Autodesk Fusion 360 part; units mm, degrees
(part 5 of 9)
sketch "Adapter Washer 4 Outer" plane through (-21.2132, -21.2132, 0) normal (0.707107, 0.707107, 0) x (0, 0, 1) in component "REF M4 Adapter Fasteners"
  circle A0 centre (22.6274, -22.6274) radius 4.5
  circle A1 centre (22.6274, -22.6274) radius 2.15
  dimension "d1308" = 22.6274
  dimension "d1309" = 22.6274
  dimension "d1310" = 9
  dimension "d1311" = 4.3
  measures "d1308" horizontal distance of origin A0.centre
  measures "d1309" vertical distance of origin A0.centre
  measures "d1310" diameter of A0
  measures "d1311" diameter of A1
extrude "Adapter Washer 4" add sketch "Adapter Washer 4 Outer" along normal blind 1 separate body makes body 52 in component "REF M4 Adapter Fasteners"
ref_plane "WorkPlane16" through (-3.182, -3.182, 12.125) normal (0.707107, 0.707107, 0) x (0, 0, 1) in component "REF M4 Adapter Fasteners"
sketch "Adapter Nut Hex 4" plane through (-3.182, -3.182, 0) normal (0.707107, 0.707107, 0) x (0, 0, 1) in component "REF M4 Adapter Fasteners"
  circle A0 centre (22.6274, -22.6274) radius 4.0415 construction
  line L0 (26.6689, -22.6274) -> (24.6481, -19.1274)
  line L1 (24.6481, -19.1274) -> (20.6067, -19.1274)
  line L2 (20.6067, -19.1274) -> (18.586, -22.6274)
  line L3 (18.586, -22.6274) -> (20.6067, -26.1274)
  line L4 (20.6067, -26.1274) -> (24.6481, -26.1274)
  line L5 (24.6481, -26.1274) -> (26.6689, -22.6274)
  dimension "d1316" = 22.6274
  dimension "d1317" = 22.6274
  dimension "d1318" = 8.0829
  constraint coincident A0 L0.start
  constraint coincident A0 L0.end
  constraint coincident A0 L1.end
  constraint coincident A0 L2.end
  constraint coincident A0 L3.end
  constraint coincident A0 L4.end
  constraint equal L0 L1
  constraint equal L0 L2
  constraint equal L0 L3
  constraint equal L0 L4
  constraint equal L0 L5
  constraint horizontal L1
  measures "d1316" horizontal distance of origin A0.centre
  measures "d1317" vertical distance of origin A0.centre
  measures "d1318" diameter of A0
extrude "Adapter Nut 4" add sketch "Adapter Nut Hex 4" along normal blind 3.2 separate body makes body 53 in component "REF M4 Adapter Fasteners"
sketch "Nut Thread Clearance 4" plane through (-3.182, -3.182, 0) normal (0.707107, 0.707107, 0) x (0, 0, 1) in component "REF M4 Adapter Fasteners"
  circle A0 centre (22.6274, -22.6274) radius 2.15
  dimension "d1321" = 22.6274
  dimension "d1322" = 22.6274
  dimension "d1323" = 4.3
  measures "d1321" horizontal distance of origin A0.centre
  measures "d1322" vertical distance of origin A0.centre
  measures "d1323" diameter of A0
extrude "Nut Bore 4" cut sketch "Nut Thread Clearance 4" along normal blind 3.2 bodies 53 in component "REF M4 Adapter Fasteners"
ref_plane "WorkPlane1" through (0, 0, 12.125) normal (0.707107, 0.707107, 0) x (0, 0, 1) in component "REF M3 Support Fasteners"
sketch "M3 Pattern Axis" plane through (0, 0, 0) normal (0.707107, 0.707107, 0) x (0, 0, 1) in component "REF M3 Support Fasteners"
  circle A0 centre (0, 0) radius 0.5
  dimension "d1328" = 1
  measures "d1328" diameter of A0
ref_plane "WorkPlane2" through (-6.1518, -6.1518, 12.125) normal (0.707107, 0.707107, 0) x (0, 0, 1) in component "REF M3 Support Fasteners"
sketch "M3 Shank Profile" plane through (-6.1518, -6.1518, 0) normal (0.707107, 0.707107, 0) x (0, 0, 1) in component "REF M3 Support Fasteners"
  line L0 (0, 0) -> (17, 0) construction
  circle A0 centre (17, 0) radius 1.5
  dimension "d1331" = 17
  dimension "d1332" = 3
  constraint horizontal L0
  measures "d1331" distance of L0.start L0.end
  measures "d1332" diameter of A0
extrude "M3 Shank" add sketch "M3 Shank Profile" along normal blind 45 separate body makes body 54 in component "REF M3 Support Fasteners"
ref_plane "WorkPlane3" through (25.668, 25.668, 12.125) normal (0.707107, 0.707107, 0) x (0, 0, 1) in component "REF M3 Support Fasteners"
sketch "M3 Head Profile" plane through (25.668, 25.668, 0) normal (0.707107, 0.707107, 0) x (0, 0, 1) in component "REF M3 Support Fasteners"
  line L0 (0, 0) -> (17, 0) construction
  circle A0 centre (17, 0) radius 2.75
  dimension "d1337" = 17
  dimension "d1338" = 5.5
  constraint horizontal L0
  measures "d1337" distance of L0.start L0.end
  measures "d1338" diameter of A0
extrude "M3 Head" add sketch "M3 Head Profile" along normal blind 3 separate body makes body 55 in component "REF M3 Support Fasteners"
ref_plane "WorkPlane4" through (25.3144, 25.3144, 12.125) normal (0.707107, 0.707107, 0) x (0, 0, 1) in component "REF M3 Support Fasteners"
sketch "Rear M3 Washer Profile" plane through (25.3144, 25.3144, 0) normal (0.707107, 0.707107, 0) x (0, 0, 1) in component "REF M3 Support Fasteners"
  line L0 (0, 0) -> (17, 0) construction
  circle A0 centre (17, 0) radius 3.5
  circle A1 centre (17, 0) radius 1.65
  dimension "d1343" = 17
  dimension "d1344" = 7
  dimension "d1345" = 3.3
  constraint horizontal L0
  measures "d1343" distance of L0.start L0.end
  measures "d1344" diameter of A0
  measures "d1345" diameter of A1
extrude "Rear M3 Washer" add sketch "Rear M3 Washer Profile" along normal blind 0.5 separate body makes body 56 in component "REF M3 Support Fasteners"
ref_plane "WorkPlane5" through (-2.1213, -2.1213, 12.125) normal (0.707107, 0.707107, 0) x (0, 0, 1) in component "REF M3 Support Fasteners"
sketch "Front M3 Washer Profile" plane through (-2.1213, -2.1213, 0) normal (0.707107, 0.707107, 0) x (0, 0, 1) in component "REF M3 Support Fasteners"
  line L0 (0, 0) -> (17, 0) construction
  circle A0 centre (17, 0) radius 3.5
  circle A1 centre (17, 0) radius 1.65
  dimension "d1350" = 17
  dimension "d1351" = 7
  dimension "d1352" = 3.3
  constraint horizontal L0
  measures "d1350" distance of L0.start L0.end
  measures "d1351" diameter of A0
  measures "d1352" diameter of A1
extrude "Front M3 Washer" add sketch "Front M3 Washer Profile" along normal blind 0.5 separate body makes body 57 in component "REF M3 Support Fasteners"
ref_plane "WorkPlane6" through (-4.9497, -4.9497, 12.125) normal (0.707107, 0.707107, 0) x (0, 0, 1) in component "REF M3 Support Fasteners"
sketch "Front M3 Nyloc Envelope Profile" plane through (-4.9497, -4.9497, 0) normal (0.707107, 0.707107, 0) x (0, 0, 1) in component "REF M3 Support Fasteners"
  line L0 (0, 0) -> (17, 0) construction
  circle A0 centre (17, 0) radius 3.18
  circle A1 centre (17, 0) radius 1.65
  dimension "d1357" = 17
  dimension "d1358" = 6.36
  dimension "d1359" = 3.3
  constraint horizontal L0
  measures "d1357" distance of L0.start L0.end
  measures "d1358" diameter of A0
  measures "d1359" diameter of A1
extrude "Front M3 Nyloc Envelope" add sketch "Front M3 Nyloc Envelope Profile" along normal blind 4 separate body makes body 58 in component "REF M3 Support Fasteners"
pattern_circular "Three M3 Support Sets" count 3 over 360 about axis through (0, 0, 0) along (0.707107, 0.707107, 0) of "M3 Shank", "M3 Head", "Rear M3 Washer", "Front M3 Washer", "Front M3 Nyloc Envelope" makes body 59 at (26.4156, 3.7072, -9.1843) makes body 60 at (38.5579, 14.1923, -9.631) makes body 61 at (37.5691, 13.0597, -9.7105) makes body 62 at (10.487, -14.0225, -9.7105) makes body 63 at (8.453, -16.4669, -9.8079) makes body 64 at (5.063, 25.0597, -7.1178) makes body 65 at (15.0384, 39.126, -9.992) makes body 66 at (13.2406, 37.3882, -10.1537) makes body 67 at (-13.8416, 10.306, -10.1537) makes body 68 at (-16.243, 8.2291, -10.3563) in component "REF M3 Support Fasteners"
ref_plane "WorkPlane25" through (12.125, 0, 0) normal (0, -1, 0) x (1, 0, 0) in component "B Moving Body"
ref_plane "WorkPlane26" through (12.125, -75, 0) normal (0, -1, 0) x (1, 0, 0) in component "B Moving Body"
ref_plane "WorkPlane27" through (-24.7487, -24.7487, 12.125) normal (0.707107, 0.707107, 0) x (0, 0, 1) in component "B Moving Body"
ref_plane "WorkPlane33" through (0, 0, -35) normal (0, 0, 1) x (1, 0, 0) in component "A Housing"
sketch "PRINT-FIRST-A0-rim Crop Footprint" plane through (0, 0, -35) normal (0, 0, 1) x (1, 0, 0) in component "A Housing"
  line L0 (55, 66.5) -> (130, 66.5)
  line L1 (130, 66.5) -> (130, 75)
  line L2 (130, 75) -> (55, 75)
  line L3 (55, 75) -> (55, 66.5)
  dimension "d1451" = 55
  dimension "d1452" = 66.5
  dimension "d1453" = 130
  dimension "d1454" = 66.5
  dimension "d1455" = 130
  dimension "d1456" = 75
  dimension "d1457" = 55
  dimension "d1458" = 75
  measures "d1451" horizontal distance of origin L0.start
  measures "d1452" vertical distance of origin L0.start
  measures "d1453" horizontal distance of origin L0.end
  measures "d1454" vertical distance of origin L0.end
  measures "d1455" horizontal distance of origin L1.end
  measures "d1456" vertical distance of origin L1.end
  measures "d1457" horizontal distance of origin L2.end
  measures "d1458" vertical distance of origin L2.end
extrude "PRINT-FIRST-A0-rim Retain Full Bay" [suppressed] in component "A Housing"
ref_plane "WorkPlane34" through (63.7103, 63.7103, 12.125) normal (0.707107, 0.707107, 0) x (0, 0, 1) in component "A Housing"
sketch "PRINT-FIRST-A0-rim Level Bed Boundary" plane through (63.7103, 63.7103, 0) normal (0.707107, 0.707107, 0) x (0, 0, 1) in component "A Housing"
  line L0 (-200, -200) -> (200, -200)
  line L1 (200, -200) -> (200, 200)
  line L2 (200, 200) -> (-200, 200)
  line L3 (-200, 200) -> (-200, -200)
  line L4 (-200, -200) -> (200, 200) construction
  dimension "d1463" = 400
  dimension "d1464" = 400
  constraint horizontal L0
  constraint vertical L1
  constraint horizontal L2
  constraint vertical L3
  constraint midpoint origin L4
  measures "d1463" distance of L0.start L0.end
  measures "d1464" distance of L0.end L1.end
extrude "PRINT-FIRST-A0-rim Level Bed Intersect" [suppressed] in component "A Housing"
ref_plane "WorkPlane35" through (0, 0, 66.5) normal (0, 0, 1) x (1, 0, 0) in component "A Housing"
sketch "PRINT-FIRST-A90-brace Crop Footprint" plane through (0, 0, 66.5) normal (0, 0, 1) x (1, 0, 0) in component "A Housing"
  line L0 (48, -35) -> (130, -35)
  line L1 (130, -35) -> (130, 35)
  line L2 (130, 35) -> (48, 35)
  line L3 (48, 35) -> (48, -35)
  dimension "d1469" = 48
  dimension "d1470" = 35
  dimension "d1471" = 130
  dimension "d1472" = 35
  dimension "d1473" = 130
  dimension "d1474" = 35
  dimension "d1475" = 48
  dimension "d1476" = 35
  measures "d1469" horizontal distance of origin L0.start
  measures "d1470" vertical distance of origin L0.start
  measures "d1471" horizontal distance of origin L0.end
  measures "d1472" vertical distance of origin L0.end
  measures "d1473" horizontal distance of origin L1.end
  measures "d1474" vertical distance of origin L1.end
  measures "d1475" horizontal distance of origin L2.end
  measures "d1476" vertical distance of origin L2.end
extrude "PRINT-FIRST-A90-brace Retain Full Bay" [suppressed] in component "A Housing"
ref_plane "WorkPlane36" through (35.426, 35.426, 12.125) normal (0.707107, 0.707107, 0) x (0, 0, 1) in component "A Housing"
sketch "PRINT-FIRST-A90-brace Level Bed Boundary" plane through (35.426, 35.426, 0) normal (0.707107, 0.707107, 0) x (0, 0, 1) in component "A Housing"
  line L0 (-200, -200) -> (200, -200)
  line L1 (200, -200) -> (200, 200)
  line L2 (200, 200) -> (-200, 200)
  line L3 (-200, 200) -> (-200, -200)
  line L4 (-200, -200) -> (200, 200) construction
  dimension "d1481" = 400
  dimension "d1482" = 400
  constraint horizontal L0
  constraint vertical L1
  constraint horizontal L2
  constraint vertical L3
  constraint midpoint origin L4
  measures "d1481" distance of L0.start L0.end
  measures "d1482" distance of L0.end L1.end
extrude "PRINT-FIRST-A90-brace Level Bed Intersect" [suppressed] in component "A Housing"
delete_body "RemoveBody1" bodies 69 in component "A Housing"
ref_plane "WorkPlane28" through (12.125, 0, 0) normal (0, -1, 0) x (1, 0, 0) in component "B Moving Body"
ref_plane "WorkPlane29" through (12.125, -75, 0) normal (0, -1, 0) x (1, 0, 0) in component "B Moving Body"
sketch "B Driver Pad 1 Slot" plane through (0, -75, 0) normal (0, -1, 0) x (-1, 0, 0) in component "B Moving Body"
  line L0 (43, 28.6274) -> (36.5, 28.6274)
  arc A0 (36.5, 28.6274) -> (36.5, 16.6274) centre (36.5, 22.6274) ccw
  line L1 (36.5, 16.6274) -> (43, 16.6274)
  arc A1 (43, 16.6274) -> (43, 28.6274) centre (43, 22.6274) ccw
  line L2 (43, 22.6274) -> (36.5, 22.6274) construction
  point P0 (43, 22.6274)
  dimension "d1489" = 43
  dimension "d1490" = 22.6274
  dimension "d1491" = 12
  dimension "d1492" = 6.5
  constraint coincident P0 A1.centre
  constraint tangent L0 A0
  constraint tangent A0 L1
  constraint tangent L1 A1
  constraint tangent L0 A1
  constraint parallel L0 L1
  constraint horizontal L2
  measures "d1489" horizontal distance of origin A1.centre
  measures "d1490" vertical distance of origin A1.centre
  measures "d1491" diameter of A0
  measures "d1492" distance of P0 A0.centre
extrude "B Driver Pad 1" add sketch "B Driver Pad 1 Slot" against normal blind 6.5 bodies 4 in component "B Moving Body"
sketch "B Driver Pad 2 Slot" plane through (0, -75, 0) normal (0, -1, 0) x (-1, 0, 0) in component "B Moving Body"
  line L0 (43, -16.6274) -> (36.5, -16.6274)
  arc A0 (36.5, -16.6274) -> (36.5, -28.6274) centre (36.5, -22.6274) ccw
  line L1 (36.5, -28.6274) -> (43, -28.6274)
  arc A1 (43, -28.6274) -> (43, -16.6274) centre (43, -22.6274) ccw
  line L2 (43, -22.6274) -> (36.5, -22.6274) construction
  point P0 (43, -22.6274)
  dimension "d1495" = 43
  dimension "d1496" = 22.6274
  dimension "d1497" = 12
  dimension "d1498" = 6.5
  constraint coincident P0 A1.centre
  constraint tangent L0 A0
  constraint tangent A0 L1
  constraint tangent L1 A1
  constraint tangent L0 A1
  constraint parallel L0 L1
  constraint horizontal L2
  measures "d1495" horizontal distance of origin A1.centre
  measures "d1496" vertical distance of origin A1.centre
  measures "d1497" diameter of A0
  measures "d1498" distance of P0 A0.centre
extrude "B Driver Pad 2" add sketch "B Driver Pad 2 Slot" against normal blind 6.5 bodies 4 in component "B Moving Body"
sketch "B Driver Pad 3 Slot" plane through (0, -75, 0) normal (0, -1, 0) x (-1, 0, 0) in component "B Moving Body"
  line L0 (107, -16.6274) -> (100.5, -16.6274)
  arc A0 (100.5, -16.6274) -> (100.5, -28.6274) centre (100.5, -22.6274) ccw
  line L1 (100.5, -28.6274) -> (107, -28.6274)
  arc A1 (107, -28.6274) -> (107, -16.6274) centre (107, -22.6274) ccw
  line L2 (107, -22.6274) -> (100.5, -22.6274) construction
  point P0 (107, -22.6274)
  dimension "d1501" = 107
  dimension "d1502" = 22.6274
  dimension "d1503" = 12
  dimension "d1504" = 6.5
  constraint coincident P0 A1.centre
  constraint tangent L0 A0
  constraint tangent A0 L1
  constraint tangent L1 A1
  constraint tangent L0 A1
  constraint parallel L0 L1
  constraint horizontal L2
  measures "d1501" horizontal distance of origin A1.centre
  measures "d1502" vertical distance of origin A1.centre
  measures "d1503" diameter of A0
  measures "d1504" distance of P0 A0.centre
extrude "B Driver Pad 3" add sketch "B Driver Pad 3 Slot" against normal blind 6.5 bodies 4 in component "B Moving Body"
sketch "B Driver Pad 4 Slot" plane through (0, -75, 0) normal (0, -1, 0) x (-1, 0, 0) in component "B Moving Body"
  line L0 (107, 28.6274) -> (100.5, 28.6274)
  arc A0 (100.5, 28.6274) -> (100.5, 16.6274) centre (100.5, 22.6274) ccw
  line L1 (100.5, 16.6274) -> (107, 16.6274)
  arc A1 (107, 16.6274) -> (107, 28.6274) centre (107, 22.6274) ccw
  line L2 (107, 22.6274) -> (100.5, 22.6274) construction
  point P0 (107, 22.6274)
  dimension "d1507" = 107
  dimension "d1508" = 22.6274
  dimension "d1509" = 12
  dimension "d1510" = 6.5
  constraint coincident P0 A1.centre
  constraint tangent L0 A0
  constraint tangent A0 L1
  constraint tangent L1 A1
  constraint tangent L0 A1
  constraint parallel L0 L1
  constraint horizontal L2
  measures "d1507" horizontal distance of origin A1.centre
  measures "d1508" vertical distance of origin A1.centre
  measures "d1509" diameter of A0
  measures "d1510" distance of P0 A0.centre
extrude "B Driver Pad 4" add sketch "B Driver Pad 4 Slot" against normal blind 6.5 bodies 4 in component "B Moving Body"
ref_plane "WorkPlane30" through (-24.7487, -24.7487, 12.125) normal (0.707107, 0.707107, 0) x (0, 0, 1) in component "B Moving Body"
sketch "B Mount Driver Axes" plane through (-24.7487, -24.7487, 0) normal (0.707107, 0.707107, 0) x (0, 0, 1) in component "B Moving Body"
  circle A0 centre (22.6274, 22.6274) radius 2.5
  circle A1 centre (-22.6274, 22.6274) radius 2.5
  circle A2 centre (-22.6274, -22.6274) radius 2.5
  circle A3 centre (22.6274, -22.6274) radius 2.5
  dimension "d1515" = 22.6274
  dimension "d1516" = 22.6274
  dimension "d1517" = 5
  dimension "d1518" = 22.6274
  dimension "d1519" = 22.6274
  dimension "d1520" = 5
  dimension "d1521" = 22.6274
  dimension "d1522" = 22.6274
  dimension "d1523" = 5
  dimension "d1524" = 22.6274
  dimension "d1525" = 22.6274
  dimension "d1526" = 5
  measures "d1515" horizontal distance of origin A0.centre
  measures "d1516" vertical distance of origin A0.centre
  measures "d1517" diameter of A0
  measures "d1518" horizontal distance of origin A1.centre
  measures "d1519" vertical distance of origin A1.centre
  measures "d1520" diameter of A1
  measures "d1521" horizontal distance of origin A2.centre
  measures "d1522" vertical distance of origin A2.centre
  measures "d1523" diameter of A2
  measures "d1524" horizontal distance of origin A3.centre
  measures "d1525" vertical distance of origin A3.centre
  measures "d1526" diameter of A3
extrude "B Four Reinforced Driver Passages" cut sketch "B Mount Driver Axes" against normal blind 260 bodies 4 in component "B Moving Body"
component "D Rear Bearing Holder" placed x (1, 0, 0) y (0, 1, 0) z (0, 0, 1) at (0, 0, 0)
component "C Front Bearing Cap" placed x (1, 0, 0) y (0, 1, 0) z (0, 0, 1) at (0, 0, 0)
component "E Rear Bearing Cap" placed x (1, 0, 0) y (0, 1, 0) z (0, 0, 1) at (0, 0, 0)
component "F Metal Hub Adapter" placed x (1, 0, 0) y (0, 1, 0) z (0, 0, 1) at (0, 0, 0)
component "REF Two 608 Bearings" placed x (1, 0, 0) y (0, 1, 0) z (0, 0, 1) at (0, 0, 0)
component "REF Steel Shaft 8 x 60" placed x (1, 0, 0) y (0, 1, 0) z (0, 0, 1) at (0, 0, 0)
component "REF Inner Ring Spacers" placed x (1, 0, 0) y (0, 1, 0) z (0, 0, 1) at (0, 0, 0)
component "REF Split Collar Envelopes" placed x (1, 0, 0) y (0, 1, 0) z (0, 0, 1) at (0, 0, 0)
component "REF Metal Support Spacers" placed x (1, 0, 0) y (0, 1, 0) z (0, 0, 1) at (0, 0, 0)
component "REF Hub Compression Sleeves" placed x (1, 0, 0) y (0, 1, 0) z (0, 0, 1) at (0, 0, 0)
component "REF Sonic Hub Envelope" placed x (1, 0, 0) y (0, 1, 0) z (0, 0, 1) at (0, 0, 0)
component "REF M4 Hub Screws" placed x (1, 0, 0) y (0, 1, 0) z (0, 0, 1) at (0, 0, 0)
component "REF M4 Adapter Fasteners" placed x (1, 0, 0) y (0, 1, 0) z (0, 0, 1) at (0, 0, 0)
component "REF M3 Support Fasteners" placed x (1, 0, 0) y (0, 1, 0) z (0, 0, 1) at (0, 0, 0)
component "A Housing" placed x (1, 0, 0) y (0, 1, 0) z (0, 0, 1) at (0, 0, 0)
component "B Moving Body" placed x (1, 0, 0) y (0, 1, 0) z (0, 0, 1) at (0, 0, 0)
equation "bodyWidth = 150 mm" comment "Regular octagon across flats; corner diameter is larger."
equation "bodyLength = 260 mm" comment "Overall straight length of the shared master blank."
equation "splitAngle = 45 deg" comment "Keep this lesson angle at45 degrees."
equation "faceGap = 1 mm" comment "Gap between the two printed joint faces."
equation "wall = 4.5 mm" comment "Integrated shell and side brace radial thickness."
equation "faceHalfWidth = bodyWidth * ( sqrt(2) - 1 ) / 2" comment "Half-width of each outer planar facet."
equation "memberWidth = 8 mm" comment "Nominal brace and corner chord width in a facet."
equation "nodeHalfWidth = faceHalfWidth - memberWidth / 2" comment "Chord centerlines measured from facet center."
equation "jointNodeQ = 7 mm" comment "First truss skeleton row from the center joint plane."
equation "endRim = 10 mm" comment "Uncut axial rim at each distant end."
equation "endNodeX = bodyLength / 2 - endRim + memberWidth / 2" comment "Last skeleton row before aperture inset."
equation "apertureRadius = 1.5 mm" comment "Rounded internal corners at triangular openings."
equation "spokeWidth = 10 mm" comment "Width of each deep bearing bulkhead spoke."
equation "spokeDepth = 18 mm" comment "Bulkhead depth normal to the diagonal joint face."
equation "carrierOD = 52 mm" comment "Outside of integrated A front bearing carrier."
equation "rearCarrierClearance = 46 mm" comment "Internal carrier relief above front bearing shoulder."
equation "tubeCornerChamfer = 0.5 mm" comment "Exposed outside octagon corner bevel."
equation "tubeRimChamfer = 0.3 mm" comment "End rim and print-contact edge relief."
equation "cordStation = bodyLength / 2 - endRim / 2" comment "Load-test cord port center measured along body X."
equation "bearingOD = 22 mm" comment "608 measured outside diameter."
equation "bearingID = 8 mm" comment "608 bore."
equation "bearingWidth = 7 mm" comment "608 width."
equation "seatAllowance = 0.2 mm" comment "Trial DIAMETRAL clearance; choose with printed coupon."
equation "seatDiameter = bearingOD + seatAllowance" comment "Measured fit controls this."
equation "coreOD = 44 mm" comment "Bearing holder outer diameter."
equation "raceRelief = 19.5 mm" comment "Outer-ring shoulder opening; verify seals."
equation "frontSeatDepth = 7.1 mm" comment "0.1 mm outer-ring axial allowance."
equation "rearSeatDepth = 7.2 mm" comment "0.2 mm outer-ring axial float."
equation "shoulder = 3 mm" comment "Backing behind each bearing seat."
equation "supportSpacer = 12 mm" comment "Purchased metal M3 spacer length."
equation "supportCircle = 34 mm" comment "Three M3 support bolts."
equation "supportSpacerOD = 6 mm" comment "Purchased spacer outside diameter."
equation "capThickness = 3 mm" comment "Both printed outer-ring retaining caps."
equation "m3Clearance = 3.3 mm" comment "M3 through holes."
equation "m4Clearance = 4.3 mm" comment "M4 through holes."
equation "qFront = faceGap / 2" comment "Front bearing starts at A mating face."
equation "qFrontBack = qFront + frontSeatDepth + shoulder" comment "End of integrated A holder."
equation "qRearBase = qFrontBack + supportSpacer" comment "Start of removable rear holder."
equation "qRearBearing = qRearBase + shoulder" comment "Rear bearing inner end."
equation "qRearEnd = qRearBearing + rearSeatDepth" comment "Rear holder outer end."
equation "bearingSpacing = qRearBearing - qFront" comment "Derived support-center spacing, not a bearing rating."
equation "mountOD = 76 mm" comment "B mount and F flange outside diameter."
equation "mountCircle = 64 mm" comment "Four M4 attachment holes."
equation "mountOpening = 50.3 mm" comment "B through opening."
equation "hubFace = -23 mm" comment "Metal hub flat mounting face."
equation "adapterThickness = 6 mm" comment "F flange and metal compression sleeve length."
equation "pilotDiameter = 50 mm" comment "F shallow centering pilot."
equation "pilotInside = 34 mm" comment "Clearance around metal hub."
equation "pilotHeight = 2 mm" comment "Short pilot only."
equation "hubHoleSpacing = 16 mm" comment "Metal Sonic hub square hole spacing."
equation "sleeveOD = 8 mm" comment "M4 metal compression sleeves."
equation "sleeveAllowance = 0.2 mm" comment "Trial DIAMETRAL sleeve clearance."
equation "shaftClearance = 8.5 mm" comment "F clearance hole; not a bearing."
equation "nutAF = 7.2 mm" comment "M4 nominal 7 AF nut trial pocket."
equation "nutDepth = 4 mm" comment "Open front M4 nut pocket."
equation "rootRadius = 1 mm" comment "Hub-to-wall blend."
equation "entryChamfer = 0.4 mm" comment "Assembly lead-in."
equation "bedRelief = 0.3 mm" comment "Bed-contact edge allowance."
equation "d59 = bodyWidth"
equation "d60 = bodyLength"
equation "d62 = splitAngle"
equation "d64 = -faceGap / 2"
equation "d65 = -faceGap / 2"
equation "d66 = wall"
equation "d67 = wall"
equation "d70 = bodyWidth / 2"
equation "d72 = abs(( 1 ) * ( ( ( 1 ) * jointNodeQ * sqrt(2) - bodyWidth / 2 * cos(0 deg) + ( ( -1 ) * nodeHalfWidth ) * sin(0 deg) ) + ( 0 ) * ( ( 1 ) * endNodeX - ( ( 1 ) * jointNodeQ * sqrt(2) - bodyWidth / 2 * cos(0 deg) + ( ( -1 ) * nodeHalfWidth ) * sin(0 deg) ) ) ) + ( 0 ) * ( ( -1 ) * nodeHalfWidth ))"
equation "d73 = abs(( 0 ) * ( ( ( 1 ) * jointNodeQ * sqrt(2) - bodyWidth / 2 * cos(0 deg) + ( ( -1 ) * nodeHalfWidth ) * sin(0 deg) ) + ( 0 ) * ( ( 1 ) * endNodeX - ( ( 1 ) * jointNodeQ * sqrt(2) - bodyWidth / 2 * cos(0 deg) + ( ( -1 ) * nodeHalfWidth ) * sin(0 deg) ) ) ) + ( -1 ) * ( ( -1 ) * nodeHalfWidth ))"
equation "d74 = abs(( 1 ) * ( ( ( 1 ) * jointNodeQ * sqrt(2) - bodyWidth / 2 * cos(0 deg) + ( ( 1 ) * nodeHalfWidth ) * sin(0 deg) ) + ( 0 ) * ( ( 1 ) * endNodeX - ( ( 1 ) * jointNodeQ * sqrt(2) - bodyWidth / 2 * cos(0 deg) + ( ( 1 ) * nodeHalfWidth ) * sin(0 deg) ) ) ) + ( 0 ) * ( ( 1 ) * nodeHalfWidth ))"
equation "d75 = abs(( 0 ) * ( ( ( 1 ) * jointNodeQ * sqrt(2) - bodyWidth / 2 * cos(0 deg) + ( ( 1 ) * nodeHalfWidth ) * sin(0 deg) ) + ( 0 ) * ( ( 1 ) * endNodeX - ( ( 1 ) * jointNodeQ * sqrt(2) - bodyWidth / 2 * cos(0 deg) + ( ( 1 ) * nodeHalfWidth ) * sin(0 deg) ) ) ) + ( -1 ) * ( ( 1 ) * nodeHalfWidth ))"
equation "d76 = abs(( 1 ) * ( ( ( 1 ) * jointNodeQ * sqrt(2) - bodyWidth / 2 * cos(0 deg) + ( ( -1 ) * nodeHalfWidth ) * sin(0 deg) ) + ( 0.666666666666667 ) * ( ( 1 ) * endNodeX - ( ( 1 ) * jointNodeQ * sqrt(2) - bodyWidth / 2 * cos(0 deg) + ( ( -1 ) * nodeHalfWidth ) * sin(0 deg) ) ) ) + ( 0 ) * ( ( -1 ) * nodeHalfWidth ))"
equation "d77 = abs(( 0 ) * ( ( ( 1 ) * jointNodeQ * sqrt(2) - bodyWidth / 2 * cos(0 deg) + ( ( -1 ) * nodeHalfWidth ) * sin(0 deg) ) + ( 0.666666666666667 ) * ( ( 1 ) * endNodeX - ( ( 1 ) * jointNodeQ * sqrt(2) - bodyWidth / 2 * cos(0 deg) + ( ( -1 ) * nodeHalfWidth ) * sin(0 deg) ) ) ) + ( -1 ) * ( ( -1 ) * nodeHalfWidth ))"
equation "d78 = -memberWidth / 2"
equation "d79 = -( wall + 0.2 mm )"
equation "d81 = abs(( 1 ) * ( ( ( 1 ) * jointNodeQ * sqrt(2) - bodyWidth / 2 * cos(0 deg) + ( ( 1 ) * nodeHalfWidth ) * sin(0 deg) ) + ( 0 ) * ( ( 1 ) * endNodeX - ( ( 1 ) * jointNodeQ * sqrt(2) - bodyWidth / 2 * cos(0 deg) + ( ( 1 ) * nodeHalfWidth ) * sin(0 deg) ) ) ) + ( 0 ) * ( ( 1 ) * nodeHalfWidth ))"
equation "d82 = abs(( 0 ) * ( ( ( 1 ) * jointNodeQ * sqrt(2) - bodyWidth / 2 * cos(0 deg) + ( ( 1 ) * nodeHalfWidth ) * sin(0 deg) ) + ( 0 ) * ( ( 1 ) * endNodeX - ( ( 1 ) * jointNodeQ * sqrt(2) - bodyWidth / 2 * cos(0 deg) + ( ( 1 ) * nodeHalfWidth ) * sin(0 deg) ) ) ) + ( -1 ) * ( ( 1 ) * nodeHalfWidth ))"
equation "d83 = abs(( 1 ) * ( ( ( 1 ) * jointNodeQ * sqrt(2) - bodyWidth / 2 * cos(0 deg) + ( ( -1 ) * nodeHalfWidth ) * sin(0 deg) ) + ( 0.666666666666667 ) * ( ( 1 ) * endNodeX - ( ( 1 ) * jointNodeQ * sqrt(2) - bodyWidth / 2 * cos(0 deg) + ( ( -1 ) * nodeHalfWidth ) * sin(0 deg) ) ) ) + ( 0 ) * ( ( -1 ) * nodeHalfWidth ))"
equation "d84 = abs(( 0 ) * ( ( ( 1 ) * jointNodeQ * sqrt(2) - bodyWidth / 2 * cos(0 deg) + ( ( -1 ) * nodeHalfWidth ) * sin(0 deg) ) + ( 0.666666666666667 ) * ( ( 1 ) * endNodeX - ( ( 1 ) * jointNodeQ * sqrt(2) - bodyWidth / 2 * cos(0 deg) + ( ( -1 ) * nodeHalfWidth ) * sin(0 deg) ) ) ) + ( -1 ) * ( ( -1 ) * nodeHalfWidth ))"
equation "d85 = abs(( 1 ) * ( ( ( 1 ) * jointNodeQ * sqrt(2) - bodyWidth / 2 * cos(0 deg) + ( ( 1 ) * nodeHalfWidth ) * sin(0 deg) ) + ( 0.833333333333333 ) * ( ( 1 ) * endNodeX - ( ( 1 ) * jointNodeQ * sqrt(2) - bodyWidth / 2 * cos(0 deg) + ( ( 1 ) * nodeHalfWidth ) * sin(0 deg) ) ) ) + ( 0 ) * ( ( 1 ) * nodeHalfWidth ))"
equation "d86 = abs(( 0 ) * ( ( ( 1 ) * jointNodeQ * sqrt(2) - bodyWidth / 2 * cos(0 deg) + ( ( 1 ) * nodeHalfWidth ) * sin(0 deg) ) + ( 0.833333333333333 ) * ( ( 1 ) * endNodeX - ( ( 1 ) * jointNodeQ * sqrt(2) - bodyWidth / 2 * cos(0 deg) + ( ( 1 ) * nodeHalfWidth ) * sin(0 deg) ) ) ) + ( -1 ) * ( ( 1 ) * nodeHalfWidth ))"
equation "d87 = memberWidth / 2"
equation "d88 = -( wall + 0.2 mm )"
equation "d90 = abs(( 1 ) * ( ( ( 1 ) * jointNodeQ * sqrt(2) - bodyWidth / 2 * cos(0 deg) + ( ( -1 ) * nodeHalfWidth ) * sin(0 deg) ) + ( 0.666666666666667 ) * ( ( 1 ) * endNodeX - ( ( 1 ) * jointNodeQ * sqrt(2) - bodyWidth / 2 * cos(0 deg) + ( ( -1 ) * nodeHalfWidth ) * sin(0 deg) ) ) ) + ( 0 ) * ( ( -1 ) * nodeHalfWidth ))"
equation "d91 = abs(( 0 ) * ( ( ( 1 ) * jointNodeQ * sqrt(2) - bodyWidth / 2 * cos(0 deg) + ( ( -1 ) * nodeHalfWidth ) * sin(0 deg) ) + ( 0.666666666666667 ) * ( ( 1 ) * endNodeX - ( ( 1 ) * jointNodeQ * sqrt(2) - bodyWidth / 2 * cos(0 deg) + ( ( -1 ) * nodeHalfWidth ) * sin(0 deg) ) ) ) + ( -1 ) * ( ( -1 ) * nodeHalfWidth ))"
equation "d92 = abs(( 1 ) * ( ( ( 1 ) * jointNodeQ * sqrt(2) - bodyWidth / 2 * cos(0 deg) + ( ( 1 ) * nodeHalfWidth ) * sin(0 deg) ) + ( 0.833333333333333 ) * ( ( 1 ) * endNodeX - ( ( 1 ) * jointNodeQ * sqrt(2) - bodyWidth / 2 * cos(0 deg) + ( ( 1 ) * nodeHalfWidth ) * sin(0 deg) ) ) ) + ( 0 ) * ( ( 1 ) * nodeHalfWidth ))"
equation "d93 = abs(( 0 ) * ( ( ( 1 ) * jointNodeQ * sqrt(2) - bodyWidth / 2 * cos(0 deg) + ( ( 1 ) * nodeHalfWidth ) * sin(0 deg) ) + ( 0.833333333333333 ) * ( ( 1 ) * endNodeX - ( ( 1 ) * jointNodeQ * sqrt(2) - bodyWidth / 2 * cos(0 deg) + ( ( 1 ) * nodeHalfWidth ) * sin(0 deg) ) ) ) + ( -1 ) * ( ( 1 ) * nodeHalfWidth ))"
equation "d94 = abs(( 1 ) * ( ( ( 1 ) * jointNodeQ * sqrt(2) - bodyWidth / 2 * cos(0 deg) + ( ( -1 ) * nodeHalfWidth ) * sin(0 deg) ) + ( 1 ) * ( ( 1 ) * endNodeX - ( ( 1 ) * jointNodeQ * sqrt(2) - bodyWidth / 2 * cos(0 deg) + ( ( -1 ) * nodeHalfWidth ) * sin(0 deg) ) ) ) + ( 0 ) * ( ( -1 ) * nodeHalfWidth ))"
equation "d95 = abs(( 0 ) * ( ( ( 1 ) * jointNodeQ * sqrt(2) - bodyWidth / 2 * cos(0 deg) + ( ( -1 ) * nodeHalfWidth ) * sin(0 deg) ) + ( 1 ) * ( ( 1 ) * endNodeX - ( ( 1 ) * jointNodeQ * sqrt(2) - bodyWidth / 2 * cos(0 deg) + ( ( -1 ) * nodeHalfWidth ) * sin(0 deg) ) ) ) + ( -1 ) * ( ( -1 ) * nodeHalfWidth ))"
equation "d96 = -memberWidth / 2"
equation "d97 = -( wall + 0.2 mm )"
equation "d99 = abs(( 1 ) * ( ( ( 1 ) * jointNodeQ * sqrt(2) - bodyWidth / 2 * cos(0 deg) + ( ( 1 ) * nodeHalfWidth ) * sin(0 deg) ) + ( 0.833333333333333 ) * ( ( 1 ) * endNodeX - ( ( 1 ) * jointNodeQ * sqrt(2) - bodyWidth / 2 * cos(0 deg) + ( ( 1 ) * nodeHalfWidth ) * sin(0 deg) ) ) ) + ( 0 ) * ( ( 1 ) * nodeHalfWidth ))"
equation "d100 = abs(( 0 ) * ( ( ( 1 ) * jointNodeQ * sqrt(2) - bodyWidth / 2 * cos(0 deg) + ( ( 1 ) * nodeHalfWidth ) * sin(0 deg) ) + ( 0.833333333333333 ) * ( ( 1 ) * endNodeX - ( ( 1 ) * jointNodeQ * sqrt(2) - bodyWidth / 2 * cos(0 deg) + ( ( 1 ) * nodeHalfWidth ) * sin(0 deg) ) ) ) + ( -1 ) * ( ( 1 ) * nodeHalfWidth ))"
equation "d101 = abs(( 1 ) * ( ( ( 1 ) * jointNodeQ * sqrt(2) - bodyWidth / 2 * cos(0 deg) + ( ( -1 ) * nodeHalfWidth ) * sin(0 deg) ) + ( 1 ) * ( ( 1 ) * endNodeX - ( ( 1 ) * jointNodeQ * sqrt(2) - bodyWidth / 2 * cos(0 deg) + ( ( -1 ) * nodeHalfWidth ) * sin(0 deg) ) ) ) + ( 0 ) * ( ( -1 ) * nodeHalfWidth ))"
equation "d102 = abs(( 0 ) * ( ( ( 1 ) * jointNodeQ * sqrt(2) - bodyWidth / 2 * cos(0 deg) + ( ( -1 ) * nodeHalfWidth ) * sin(0 deg) ) + ( 1 ) * ( ( 1 ) * endNodeX - ( ( 1 ) * jointNodeQ * sqrt(2) - bodyWidth / 2 * cos(0 deg) + ( ( -1 ) * nodeHalfWidth ) * sin(0 deg) ) ) ) + ( -1 ) * ( ( -1 ) * nodeHalfWidth ))"
equation "d103 = abs(( 1 ) * ( ( ( 1 ) * jointNodeQ * sqrt(2) - bodyWidth / 2 * cos(0 deg) + ( ( 1 ) * nodeHalfWidth ) * sin(0 deg) ) + ( 1 ) * ( ( 1 ) * endNodeX - ( ( 1 ) * jointNodeQ * sqrt(2) - bodyWidth / 2 * cos(0 deg) + ( ( 1 ) * nodeHalfWidth ) * sin(0 deg) ) ) ) + ( 0 ) * ( ( 1 ) * nodeHalfWidth ))"
equation "d104 = abs(( 0 ) * ( ( ( 1 ) * jointNodeQ * sqrt(2) - bodyWidth / 2 * cos(0 deg) + ( ( 1 ) * nodeHalfWidth ) * sin(0 deg) ) + ( 1 ) * ( ( 1 ) * endNodeX - ( ( 1 ) * jointNodeQ * sqrt(2) - bodyWidth / 2 * cos(0 deg) + ( ( 1 ) * nodeHalfWidth ) * sin(0 deg) ) ) ) + ( -1 ) * ( ( 1 ) * nodeHalfWidth ))"
equation "d105 = memberWidth / 2"
equation "d106 = -( wall + 0.2 mm )"
equation "d109 = apertureRadius"
equation "d112 = bodyWidth / 2"
equation "d114 = abs(( 1 ) * ( ( ( 1 ) * jointNodeQ * sqrt(2) - bodyWidth / 2 * cos(45 deg) + ( ( -1 ) * nodeHalfWidth ) * sin(45 deg) ) + ( 0 ) * ( ( 1 ) * endNodeX - ( ( 1 ) * jointNodeQ * sqrt(2) - bodyWidth / 2 * cos(45 deg) + ( ( -1 ) * nodeHalfWidth ) * sin(45 deg) ) ) ) + ( 0 ) * ( ( -1 ) * nodeHalfWidth ))"
equation "d115 = abs(( 0 ) * ( ( ( 1 ) * jointNodeQ * sqrt(2) - bodyWidth / 2 * cos(45 deg) + ( ( -1 ) * nodeHalfWidth ) * sin(45 deg) ) + ( 0 ) * ( ( 1 ) * endNodeX - ( ( 1 ) * jointNodeQ * sqrt(2) - bodyWidth / 2 * cos(45 deg) + ( ( -1 ) * nodeHalfWidth ) * sin(45 deg) ) ) ) + ( -1 ) * ( ( -1 ) * nodeHalfWidth ))"
equation "d116 = abs(( 1 ) * ( ( ( 1 ) * jointNodeQ * sqrt(2) - bodyWidth / 2 * cos(45 deg) + ( ( 1 ) * nodeHalfWidth ) * sin(45 deg) ) + ( 0 ) * ( ( 1 ) * endNodeX - ( ( 1 ) * jointNodeQ * sqrt(2) - bodyWidth / 2 * cos(45 deg) + ( ( 1 ) * nodeHalfWidth ) * sin(45 deg) ) ) ) + ( 0 ) * ( ( 1 ) * nodeHalfWidth ))"
equation "d117 = abs(( 0 ) * ( ( ( 1 ) * jointNodeQ * sqrt(2) - bodyWidth / 2 * cos(45 deg) + ( ( 1 ) * nodeHalfWidth ) * sin(45 deg) ) + ( 0 ) * ( ( 1 ) * endNodeX - ( ( 1 ) * jointNodeQ * sqrt(2) - bodyWidth / 2 * cos(45 deg) + ( ( 1 ) * nodeHalfWidth ) * sin(45 deg) ) ) ) + ( -1 ) * ( ( 1 ) * nodeHalfWidth ))"
equation "d118 = abs(( 1 ) * ( ( ( 1 ) * jointNodeQ * sqrt(2) - bodyWidth / 2 * cos(45 deg) + ( ( -1 ) * nodeHalfWidth ) * sin(45 deg) ) + ( 0.333333333333333 ) * ( ( 1 ) * endNodeX - ( ( 1 ) * jointNodeQ * sqrt(2) - bodyWidth / 2 * cos(45 deg) + ( ( -1 ) * nodeHalfWidth ) * sin(45 deg) ) ) ) + ( 0 ) * ( ( -1 ) * nodeHalfWidth ))"
equation "d119 = abs(( 0 ) * ( ( ( 1 ) * jointNodeQ * sqrt(2) - bodyWidth / 2 * cos(45 deg) + ( ( -1 ) * nodeHalfWidth ) * sin(45 deg) ) + ( 0.333333333333333 ) * ( ( 1 ) * endNodeX - ( ( 1 ) * jointNodeQ * sqrt(2) - bodyWidth / 2 * cos(45 deg) + ( ( -1 ) * nodeHalfWidth ) * sin(45 deg) ) ) ) + ( -1 ) * ( ( -1 ) * nodeHalfWidth ))"
equation "d120 = -memberWidth / 2"
equation "d121 = -( wall + 0.2 mm )"
equation "d123 = abs(( 1 ) * ( ( ( 1 ) * jointNodeQ * sqrt(2) - bodyWidth / 2 * cos(45 deg) + ( ( 1 ) * nodeHalfWidth ) * sin(45 deg) ) + ( 0 ) * ( ( 1 ) * endNodeX - ( ( 1 ) * jointNodeQ * sqrt(2) - bodyWidth / 2 * cos(45 deg) + ( ( 1 ) * nodeHalfWidth ) * sin(45 deg) ) ) ) + ( 0 ) * ( ( 1 ) * nodeHalfWidth ))"
equation "d124 = abs(( 0 ) * ( ( ( 1 ) * jointNodeQ * sqrt(2) - bodyWidth / 2 * cos(45 deg) + ( ( 1 ) * nodeHalfWidth ) * sin(45 deg) ) + ( 0 ) * ( ( 1 ) * endNodeX - ( ( 1 ) * jointNodeQ * sqrt(2) - bodyWidth / 2 * cos(45 deg) + ( ( 1 ) * nodeHalfWidth ) * sin(45 deg) ) ) ) + ( -1 ) * ( ( 1 ) * nodeHalfWidth ))"
equation "d125 = abs(( 1 ) * ( ( ( 1 ) * jointNodeQ * sqrt(2) - bodyWidth / 2 * cos(45 deg) + ( ( -1 ) * nodeHalfWidth ) * sin(45 deg) ) + ( 0.333333333333333 ) * ( ( 1 ) * endNodeX - ( ( 1 ) * jointNodeQ * sqrt(2) - bodyWidth / 2 * cos(45 deg) + ( ( -1 ) * nodeHalfWidth ) * sin(45 deg) ) ) ) + ( 0 ) * ( ( -1 ) * nodeHalfWidth ))"
equation "d126 = abs(( 0 ) * ( ( ( 1 ) * jointNodeQ * sqrt(2) - bodyWidth / 2 * cos(45 deg) + ( ( -1 ) * nodeHalfWidth ) * sin(45 deg) ) + ( 0.333333333333333 ) * ( ( 1 ) * endNodeX - ( ( 1 ) * jointNodeQ * sqrt(2) - bodyWidth / 2 * cos(45 deg) + ( ( -1 ) * nodeHalfWidth ) * sin(45 deg) ) ) ) + ( -1 ) * ( ( -1 ) * nodeHalfWidth ))"
equation "d127 = abs(( 1 ) * ( ( ( 1 ) * jointNodeQ * sqrt(2) - bodyWidth / 2 * cos(45 deg) + ( ( 1 ) * nodeHalfWidth ) * sin(45 deg) ) + ( 0.666666666666667 ) * ( ( 1 ) * endNodeX - ( ( 1 ) * jointNodeQ * sqrt(2) - bodyWidth / 2 * cos(45 deg) + ( ( 1 ) * nodeHalfWidth ) * sin(45 deg) ) ) ) + ( 0 ) * ( ( 1 ) * nodeHalfWidth ))"
equation "d128 = abs(( 0 ) * ( ( ( 1 ) * jointNodeQ * sqrt(2) - bodyWidth / 2 * cos(45 deg) + ( ( 1 ) * nodeHalfWidth ) * sin(45 deg) ) + ( 0.666666666666667 ) * ( ( 1 ) * endNodeX - ( ( 1 ) * jointNodeQ * sqrt(2) - bodyWidth / 2 * cos(45 deg) + ( ( 1 ) * nodeHalfWidth ) * sin(45 deg) ) ) ) + ( -1 ) * ( ( 1 ) * nodeHalfWidth ))"
equation "d129 = memberWidth / 2"
equation "d130 = -( wall + 0.2 mm )"
equation "d132 = abs(( 1 ) * ( ( ( 1 ) * jointNodeQ * sqrt(2) - bodyWidth / 2 * cos(45 deg) + ( ( -1 ) * nodeHalfWidth ) * sin(45 deg) ) + ( 0.333333333333333 ) * ( ( 1 ) * endNodeX - ( ( 1 ) * jointNodeQ * sqrt(2) - bodyWidth / 2 * cos(45 deg) + ( ( -1 ) * nodeHalfWidth ) * sin(45 deg) ) ) ) + ( 0 ) * ( ( -1 ) * nodeHalfWidth ))"
equation "d133 = abs(( 0 ) * ( ( ( 1 ) * jointNodeQ * sqrt(2) - bodyWidth / 2 * cos(45 deg) + ( ( -1 ) * nodeHalfWidth ) * sin(45 deg) ) + ( 0.333333333333333 ) * ( ( 1 ) * endNodeX - ( ( 1 ) * jointNodeQ * sqrt(2) - bodyWidth / 2 * cos(45 deg) + ( ( -1 ) * nodeHalfWidth ) * sin(45 deg) ) ) ) + ( -1 ) * ( ( -1 ) * nodeHalfWidth ))"
equation "d134 = abs(( 1 ) * ( ( ( 1 ) * jointNodeQ * sqrt(2) - bodyWidth / 2 * cos(45 deg) + ( ( 1 ) * nodeHalfWidth ) * sin(45 deg) ) + ( 0.666666666666667 ) * ( ( 1 ) * endNodeX - ( ( 1 ) * jointNodeQ * sqrt(2) - bodyWidth / 2 * cos(45 deg) + ( ( 1 ) * nodeHalfWidth ) * sin(45 deg) ) ) ) + ( 0 ) * ( ( 1 ) * nodeHalfWidth ))"
equation "d135 = abs(( 0 ) * ( ( ( 1 ) * jointNodeQ * sqrt(2) - bodyWidth / 2 * cos(45 deg) + ( ( 1 ) * nodeHalfWidth ) * sin(45 deg) ) + ( 0.666666666666667 ) * ( ( 1 ) * endNodeX - ( ( 1 ) * jointNodeQ * sqrt(2) - bodyWidth / 2 * cos(45 deg) + ( ( 1 ) * nodeHalfWidth ) * sin(45 deg) ) ) ) + ( -1 ) * ( ( 1 ) * nodeHalfWidth ))"